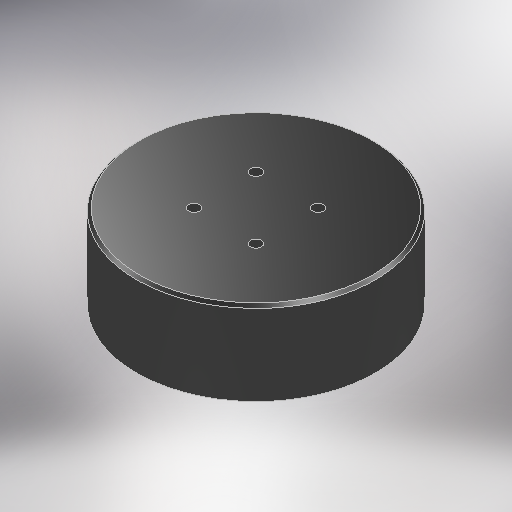
# Autodesk Inventor part: 2204_260kv
Saved by Autodesk Inventor 2025.3 (Build 293356030, 356C)
## iProperties
Created: 2026-05-04
Part Number: 2204_260kv
Material: 一般
Document SubType Name: Modeling
Designer: ibuki_ono
Density: 1 g/cm^3
Appearance: 光沢 - 黒
Author: ibuki_ono
Autodesk Inventor part; units mm, degrees
ref_plane "YZ Plane" through (0, 0, 0) normal (1, 0, 0) x (0, 1, 0)
ref_plane "XZ Plane" through (0, 0, 0) normal (0, 1, 0) x (-1, 0, 0)
ref_plane "XY Plane" through (0, 0, 0) normal (0, 0, 1) x (1, 0, 0)
sketch "スケッチ1" plane through (0, 0, 0) normal (0, 1, 0) x (-1, 0, 0)
  circle A0 centre (0, 0) radius 17
  dimension "d0" = 34
  constraints: 1 centre point, 1 coincident
  measures "d0" diameter of A0
extrude "押し出し1" add sketch "スケッチ1" along normal blind 11.9
chamfer "面取り1" distance 0.4 angle 45 1 edges at (17, 11.9, 0)
sketch "スケッチ2" plane through (0, 11.9, 0) normal (0, 1, 0) x (1, 0, 0)
  circle A0 centre (0, 0) radius 6.25 construction
  line L0 (-4.4194, -4.4194) -> (4.4194, -4.4194) construction
  line L1 (4.4194, -4.4194) -> (4.4194, 4.4194) construction
  line L2 (4.4194, 4.4194) -> (-4.4194, 4.4194) construction
  line L3 (-4.4194, 4.4194) -> (-4.4194, -4.4194) construction
  line L4 (-4.4194, -4.4194) -> (4.4194, 4.4194) construction
  line L5 (4.4194, -4.4194) -> (-4.4194, 4.4194) construction
  dimension "d6" = 12.5
  constraints: 12 end point, 5 coincident, 2 midpoint, 2 parallel, 2 perpendicular, 1 horizontal, 3 other
hole "穴1" at (-4.4194, 11.9, -4.4194) at (4.4194, 11.9, -4.4194) at (4.4194, 11.9, 4.4194) at (-4.4194, 11.9, 4.4194) direction (0, -1, 0) diameter 1.6 depth 5
